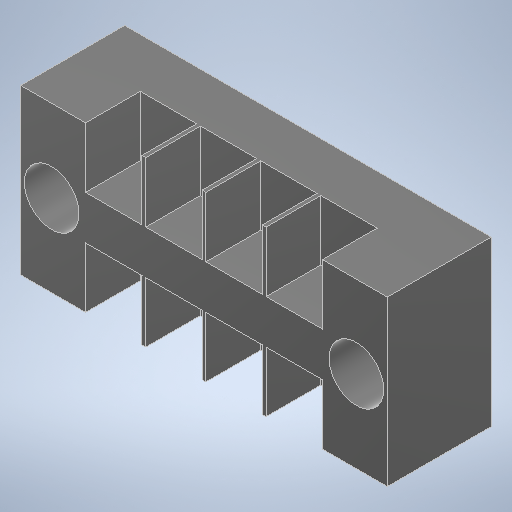
# Autodesk Inventor part: terminal
Saved by Autodesk Inventor 2025.3 (Build 293356030, 356C)
## iProperties
Created: 2025-09-05
Part Number: terminal
Material: 一般
Document SubType Name: Modeling
Designer: ibuki_ono
Density: 1 g/cm^3
Appearance: 滑らか - 黒
Author: ibuki_ono
Autodesk Inventor part; units mm, degrees
ref_plane "YZ Plane" through (0, 0, 0) normal (1, 0, 0) x (0, 1, 0)
ref_plane "XZ Plane" through (0, 0, 0) normal (0, 1, 0) x (-1, 0, 0)
ref_plane "XY Plane" through (0, 0, 0) normal (0, 0, 1) x (1, 0, 0)
sketch "スケッチ1" plane through (0, 0, 0) normal (0, 0, 1) x (1, 0, 0)
  line L0 (-33.5, -15) -> (33.5, -15)
  line L1 (33.5, -15) -> (33.5, 15)
  line L2 (33.5, 15) -> (-33.5, 15)
  line L3 (-33.5, 15) -> (-33.5, -15)
  line L4 (-33.5, -15) -> (33.5, 15) construction
  line L5 (33.5, -15) -> (-33.5, 15) construction
  point P0 (0, 0)
  dimension "d0" = 67
  dimension "d1" = 30
  constraints: 12 end point, 2 midpoint, 2 parallel, 1 horizontal, 1 perpendicular
  measures "d0" distance of L2.end L1.end
  measures "d1" distance of L1.end L0.end
extrude "押し出し1" add sketch "スケッチ1" along normal blind 19
sketch "スケッチ2" plane through (0, 0, 19) normal (0, 0, 1) x (1, 0, 0)
  line L0 (-27.85, 0) -> (27.85, 0) construction
  line L1 (-27.85, 0) -> (27.85, 0) construction
  point P0 (0, 0)
  point P1 (0, 0)
  dimension "d4" = 55.7
  dimension "d5" = 0
  constraints: 4 end point, 3 coincident, 2 horizontal, 1 collinear, 1 midpoint
  measures "d4" distance of L0.start L0.end
  measures "d5" distance between parallel lines of L0 L1
hole "穴1" at (27.85, 0, 19) at (-27.85, 0, 19) direction (0, 0, -1) diameter 5 end through all counterbore diameter 10 counterbore depth 16
sketch "スケッチ3" plane through (0, 0, 19) normal (0, 0, 1) x (1, 0, 0)
  line L0 (33.5, 15) -> (-33.5, 15) projected
  line L1 (-21.65, 15) -> (-11.35, 15)
  line L2 (-11.35, 15) -> (-11.35, 4)
  line L3 (-11.35, 4) -> (-21.65, 4)
  line L4 (-21.65, 4) -> (-21.65, 15)
  point P0 (0, 0)
  point P1 (-16.5, 4)
  dimension "d13" = 10.3
  dimension "d14" = 11
  dimension "d15" = 16.5
  constraints: 8 end point, 2 parallel, 1 horizontal, 1 midpoint, 1 perpendicular, 1 point on line
  measures "d13" distance of L2.end L3.end
  measures "d14" distance of L1.end L2.end
  measures "d15" horizontal distance of point (-16.5, 4) point (0, 0)
extrude "押し出し2" cut sketch "スケッチ3" against normal blind 10
pattern_linear "矩形状パターン1" count 4 spacing 11 along (1, 0, 0) of "押し出し2"
mirror "ミラー1" about plane through (0, 0, 0) normal (0, 1, 0) of "押し出し2", "矩形状パターン1"
